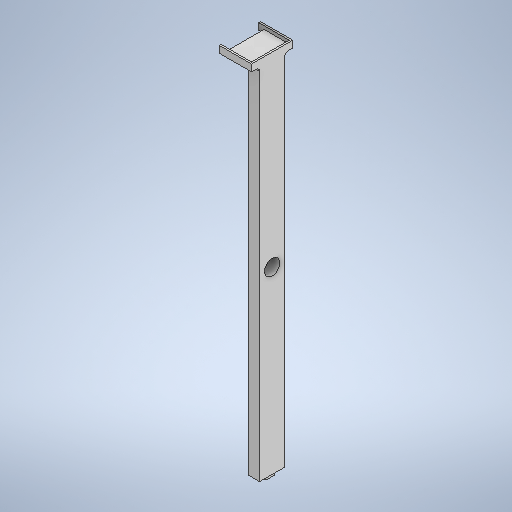
# Autodesk Inventor part: iterasi3-cetak
Saved by Autodesk Inventor 2026.2 (Build 302298010, 298A)
## iProperties
Created: 2026-11-17
Part Number: iterasi3-cetak
Material: Generic
Document SubType Name: Modeling
Designer: Acer
Density: 1 g/cm^3
Appearance: Default
Author: Acer
Autodesk Inventor part; units mm, degrees
ref_plane "YZ Plane" through (0, 0, 0) normal (1, 0, 0) x (0, 1, 0)
ref_plane "XZ Plane" through (0, 0, 0) normal (0, 1, 0) x (-1, 0, 0)
ref_plane "XY Plane" through (0, 0, 0) normal (0, 0, 1) x (1, 0, 0)
sketch "Sketch1" plane through (0, 0, 0) normal (1, 0, 0) x (0, 1, 0)
  line L0 (200, 7) -> (-200, 7)
  line L1 (-200, 7) -> (-200, -7)
  line L2 (-200, -7) -> (200, -7)
  line L3 (200, -7) -> (200, 7)
  circle A0 centre (100, 0) radius 4.3
  point P0 (0, 0)
  dimension "d2" = 14
  dimension "d4" = 8.6
  constraints: 8 end point, 2 parallel, 1 centre point, 1 horizontal, 1 perpendicular
  measures "d2" distance of L1.end L0.end
  measures "d4" diameter of A0
extrude "Extrusion1" add sketch "Sketch1" along normal blind 6
sketch "Sketch16" plane through (6, 0, 0) normal (1, 0, 0) x (0, 0, -1)
  line L0 (-7, 200) -> (-7, -200) projected
  line L1 (-7, 0) -> (7, 0)
  line L2 (7, -200) -> (7, 200) projected
  line L3 (-7, 0) -> (7, 0)
  line L4 (7, 0) -> (7, -200)
  line L5 (7, -200) -> (-7, -200)
  line L6 (-7, -200) -> (-7, 0)
  point P0 (0, 0)
  constraints: 10 end point, 2 midpoint, 2 parallel, 1 horizontal, 1 perpendicular
extrude "Extrusion11" cut sketch "Sketch16" against normal blind 10
sketch "Sketch17" plane through (6, 0, -7) normal (0, -1, 0) x (1, 0, 0)
  line L0 (-6, 0) -> (-6, 14) projected
  line L1 (0, 0) -> (-6, 0) projected
  line L2 (0, 14) -> (0, 0) projected
  line L3 (-6, 14) -> (0, 14) projected
  line L4 (-1, 9.5) -> (-5, 9.5)
  line L5 (-5, 9.5) -> (-5, 4.5)
  line L6 (-5, 4.5) -> (-1, 4.5)
  line L7 (-1, 4.5) -> (-1, 9.5)
  line L8 (-1, 9.5) -> (-5, 4.5) construction
  line L9 (-5, 9.5) -> (-1, 4.5) construction
  point P0 (-6, 7)
  point P1 (-3, 7)
  dimension "d46" = 4
  dimension "d47" = 5
  constraints: 12 end point, 2 midpoint, 2 parallel, 1 horizontal, 1 perpendicular
  measures "d46" distance of L6.end L5.end
  measures "d47" distance of L5.end L4.end
extrude "Extrusion12" add sketch "Sketch17" along normal blind 2 contours L7 L6 L5 L4
sketch "Sketch18" plane through (0, 200, 7) normal (0, 1, 0) x (1, 0, 0)
  line L0 (0, 14) -> (0, 0) projected
  line L1 (0, 0) -> (6, 0) projected
  line L2 (6, 14) -> (6, 0) projected
  line L3 (0, 14) -> (6, 14) projected
  line L4 (6, -4.5) -> (6, 18.5)
  line L5 (6, 18.5) -> (-12, 18.5)
  line L6 (-12, 18.5) -> (-12, -4.5)
  line L7 (-12, -4.5) -> (6, -4.5)
  line L8 (-12, 18.5) -> (-12, 17.5)
  line L9 (-12, 17.5) -> (-9, 17.5)
  line L10 (0, 7) -> (6, 7)
  line L11 (1, 4.5) -> (1, 9.5) projected
  line L12 (-12, -4.5) -> (-12, -3.5)
  line L13 (-12, -3.5) -> (-9, -3.5)
  line L14 (-9, 17.5) -> (-9, -3.5)
  dimension "d50" = 23
  dimension "d51" = 18
  dimension "d52" = 1
  dimension "d53" = 3
  constraints: 20 end point, 3 perpendicular, 2 horizontal, 2 midpoint, 2 symmetric about line, 2 vertical, 1 point on line
  measures "d50" distance of L4.start L4.end
  measures "d51" distance of L4.end L5.end
  measures "d52" distance of L5.end L8.end
  measures "d53" distance of L8.end L9.end
extrude "Extrusion13" add sketch "Sketch18" along normal blind 2 contours L3 L2 L10 L0 | L0 L1 L4 L7 L6 L13 L14 L9 L5 L3 | L10 L2 L1 L0
sketch "Sketch19" plane through (0, 202, 7) normal (0, 1, 0) x (1, 0, 0)
  line L0 (6, 18.5) -> (-12, 18.5) projected
  line L1 (-12, 18.5) -> (-12, 17.5) projected
  line L2 (-12, 17.5) -> (-9, 17.5) projected
  line L3 (-9, 17.5) -> (-9, -3.5) projected
  line L4 (-9, -3.5) -> (-12, -3.5) projected
  line L5 (-12, -3.5) -> (-12, -4.5) projected
  line L6 (-12, -4.5) -> (6, -4.5) projected
  line L7 (6, -4.5) -> (6, 18.5) projected
  line L8 (-12, 18.5) -> (6, 18.5)
  line L9 (6, 18.5) -> (6, 17.5)
  line L10 (5, 17.5) -> (-12, 17.5)
  line L11 (-12, 17.5) -> (-12, 18.5)
  line L12 (-12, -3.5) -> (5, -3.5)
  line L13 (6, -3.5) -> (6, -4.5)
  line L14 (6, -4.5) -> (-12, -4.5)
  line L15 (-12, -4.5) -> (-12, -3.5)
  line L16 (6, -4.5) -> (6, 18.5) projected
  line L17 (6, 18.5) -> (5, 18.5)
  line L18 (5, 17.5) -> (5, -3.5)
  line L19 (5, -4.5) -> (6, -4.5)
  line L20 (6, -4.5) -> (6, 18.5)
  point P0 (0, 7)
  dimension "d56" = 1
  constraints: 24 end point, 6 parallel, 3 horizontal, 3 perpendicular, 3 point on line
  measures "d56" distance of L19.end L19.start
extrude "Extrusion14" add sketch "Sketch19" along normal blind 1.8 contours L7 L6 L5 L4 L12 L18 L10 L2 L1 L0
fillet "Fillet1" radius 2 3 edges at (3, 200, -7) (0, 200, 0) (3, 200, 7)
body "Solid1"
